Eye Adaptor native (Autodesk Fusion 360 design; units mm, degrees)
part number: 2026-10-13-21-17-23-938
Autodesk Fusion 360 part; units mm, degrees
ref_plane "WorkPlane1" through (0, 0, -5.95) normal (0, 0, 1) x (1, 0, 0)
sketch "Base" plane through (0, 0, -5.95) normal (0, 0, 1) x (1, 0, 0)
  circle A0 centre (0, 0) radius 11.7
  dimension "d80" = 23.4
  constraint coincident A0.centre origin
  measures "d80" diameter of A0
extrude "Eye Adaptor native" add sketch "Base" along normal mid plane 1.5 makes body 1
ref_plane "WorkPlane2" through (0, -1.05, 0) normal (0, 1, 0) x (0, 0, 1)
sketch "Side lug +X" plane through (0, -1.05, 0) normal (0, 1, 0) x (1, 0, 0)
  line L0 (3.609, 5.2) -> (3.609, 1.95)
  arc A0 (3.609, 1.95) -> (5.859, -0.3) centre (5.859, 1.95) ccw
  line L1 (5.859, -0.3) -> (6.949, -0.3)
  arc A1 (6.949, -0.3) -> (8.359, 1.9497) centre (5.8593, 1.9497) ccw
  line L2 (8.359, 1.9497) -> (8.359, 5.2)
  line L3 (8.359, 5.2) -> (3.609, 5.2)
  dimension "d81" = 2.25
  dimension "d82" = 2.4997
  dimension "d83" = 5.859
  dimension "d84" = 1.95
  dimension "d85" = 5.8593
  dimension "d86" = 1.9497
  dimension "d87" = 5.2
  constraint vertical L0
  constraint horizontal L1
  constraint vertical L2
  constraint horizontal L3
  constraint tangent L0 A0
  constraint tangent A0 L1
  constraint tangent A1 L2
  measures "d81" radius of A0
  measures "d82" radius of A1
  measures "d83" horizontal distance of origin A0.centre
  measures "d84" vertical distance of origin A0.centre
  measures "d85" horizontal distance of origin A1.centre
  measures "d86" vertical distance of origin A1.centre
  measures "d87" vertical distance of origin L0.start
extrude "Side lug +X (1)" add sketch "Side lug +X" along normal mid plane 4.1 separate body makes body 2
ref_plane "WorkPlane3" through (0, -1.05, 0) normal (0, 1, 0) x (0, 0, 1)
sketch "Side lug -X" plane through (0, -1.05, 0) normal (0, 1, 0) x (1, 0, 0)
  line L0 (-3.609, 5.2) -> (-3.609, 1.95)
  arc A0 (-5.859, -0.3) -> (-3.609, 1.95) centre (-5.859, 1.95) ccw
  line L1 (-5.859, -0.3) -> (-6.949, -0.3)
  arc A1 (-8.359, 1.9497) -> (-6.949, -0.3) centre (-5.8593, 1.9497) ccw
  line L2 (-8.359, 1.9497) -> (-8.359, 5.2)
  line L3 (-8.359, 5.2) -> (-3.609, 5.2)
  dimension "d88" = 2.25
  dimension "d89" = 2.4997
  dimension "d90" = 5.859
  dimension "d91" = 1.95
  dimension "d92" = 5.8593
  dimension "d93" = 1.9497
  dimension "d94" = 5.2
  constraint vertical L0
  constraint horizontal L1
  constraint vertical L2
  constraint horizontal L3
  constraint tangent L0 A0
  constraint tangent A0 L1
  constraint tangent A1 L2
  measures "d88" radius of A0
  measures "d89" radius of A1
  measures "d90" horizontal distance of origin A0.centre
  measures "d91" vertical distance of origin A0.centre
  measures "d92" horizontal distance of origin A1.centre
  measures "d93" vertical distance of origin A1.centre
  measures "d94" vertical distance of origin L0.start
extrude "Side lug -X (1)" add sketch "Side lug -X" along normal mid plane 4.1 separate body makes body 3
ref_plane "WorkPlane4" through (0, 0, -2.1) normal (0, 0, 1) x (1, 0, 0)
sketch "Gusset +X" plane through (0, 0, -2.1) normal (0, 0, 1) x (1, 0, 0)
  line L0 (3.5, -3) -> (8.1, -3)
  line L1 (8.1, -3) -> (3.5, -7.6)
  line L2 (3.5, -7.6) -> (3.5, -3)
  dimension "d95" = 3.5
  dimension "d96" = 3
  dimension "d97" = 8.1
  dimension "d98" = 7.6
  constraint horizontal L0
  constraint vertical L2
  measures "d95" horizontal distance of origin L0.start
  measures "d96" vertical distance of origin L0.start
  measures "d97" horizontal distance of origin L0.end
  measures "d98" vertical distance of origin L1.end
extrude "Gusset +X (1)" add sketch "Gusset +X" along normal mid plane 6.2 separate body makes body 4
ref_plane "WorkPlane5" through (0, -5.5, 0) normal (0, 1, 0) x (0, 0, 1)
sketch "Gusset dome +X" plane through (0, -5.5, 0) normal (0, 1, 0) x (1, 0, 0)
  line L0 (3.5, 5.2) -> (3.5, 0.024)
  line L1 (3.5, 0.024) -> (4.0825, 0.191)
  arc A0 (4.0825, 0.191) -> (8.359, 1.95) centre (5.859, 1.95) ccw
  line L2 (8.359, 1.95) -> (8.359, 5.2)
  line L3 (8.359, 5.2) -> (3.5, 5.2)
  dimension "d99" = 2.5
  dimension "d100" = 5.859
  dimension "d101" = 1.95
  dimension "d102" = 3.5
  dimension "d103" = 5.2
  dimension "d104" = 0.024
  dimension "d105" = 4.0825
  constraint vertical L0
  constraint vertical L2
  constraint horizontal L3
  constraint tangent A0 L2
  measures "d99" radius of A0
  measures "d100" horizontal distance of origin A0.centre
  measures "d101" vertical distance of origin A0.centre
  measures "d102" horizontal distance of origin L0.start
  measures "d103" vertical distance of origin L0.start
  measures "d104" vertical distance of origin L0.end
  measures "d105" horizontal distance of origin L1.end
extrude "Gusset dome +X (1)" add sketch "Gusset dome +X" along normal mid plane 5 separate body makes body 5
combine "Combine1" operation intersect target body 4 tool bodies 5
ref_plane "WorkPlane6" through (0, 0, -2.1) normal (0, 0, 1) x (1, 0, 0)
sketch "Gusset -X" plane through (0, 0, -2.1) normal (0, 0, 1) x (1, 0, 0)
  line L0 (-3.5, -3) -> (-8.1, -3)
  line L1 (-8.1, -3) -> (-3.5, -7.6)
  line L2 (-3.5, -7.6) -> (-3.5, -3)
  dimension "d106" = 3.5
  dimension "d107" = 3
  dimension "d108" = 8.1
  dimension "d109" = 7.6
  constraint horizontal L0
  constraint vertical L2
  measures "d106" horizontal distance of origin L0.start
  measures "d107" vertical distance of origin L0.start
  measures "d108" horizontal distance of origin L0.end
  measures "d109" vertical distance of origin L1.end
extrude "Gusset -X (1)" add sketch "Gusset -X" along normal mid plane 6.2 separate body makes body 6
ref_plane "WorkPlane7" through (0, -5.5, 0) normal (0, 1, 0) x (0, 0, 1)
sketch "Gusset dome -X" plane through (0, -5.5, 0) normal (0, 1, 0) x (1, 0, 0)
  line L0 (-3.5, 5.2) -> (-3.5, 0.024)
  line L1 (-3.5, 0.024) -> (-4.0825, 0.191)
  arc A0 (-8.359, 1.95) -> (-4.0825, 0.191) centre (-5.859, 1.95) ccw
  line L2 (-8.359, 1.95) -> (-8.359, 5.2)
  line L3 (-8.359, 5.2) -> (-3.5, 5.2)
  dimension "d110" = 2.5
  dimension "d111" = 5.859
  dimension "d112" = 1.95
  dimension "d113" = 3.5
  dimension "d114" = 5.2
  dimension "d115" = 0.024
  dimension "d116" = 4.0825
  constraint vertical L0
  constraint vertical L2
  constraint horizontal L3
  constraint tangent A0 L2
  measures "d110" radius of A0
  measures "d111" horizontal distance of origin A0.centre
  measures "d112" vertical distance of origin A0.centre
  measures "d113" horizontal distance of origin L0.start
  measures "d114" vertical distance of origin L0.start
  measures "d115" vertical distance of origin L0.end
  measures "d116" horizontal distance of origin L1.end
extrude "Gusset dome -X (1)" add sketch "Gusset dome -X" along normal mid plane 5 separate body makes body 7
combine "Combine2" operation intersect target body 6 tool bodies 7
ref_plane "WorkPlane8" through (0, -5.55, 0) normal (0, 1, 0) x (0, 0, 1)
sketch "Centre lug" plane through (0, -5.55, 0) normal (0, 1, 0) x (1, 0, 0)
  line L0 (-3.5, 5.2) -> (3.5, 5.2)
  line L1 (3.5, 5.2) -> (3.5, 0)
  arc A0 (-3.5, 0) -> (3.5, 0) centre (0, 0) ccw
  line L2 (-3.5, 0) -> (-3.5, 5.2)
  dimension "d117" = 3.5
  dimension "d118" = 5.2
  constraint horizontal L0
  constraint vertical L1
  constraint vertical L2
  constraint tangent L1 A0
  constraint tangent A0 L2
  constraint coincident A0.centre origin
  measures "d117" radius of A0
  measures "d118" vertical distance of A0.centre L0.start
extrude "Centre lug (1)" add sketch "Centre lug" along normal mid plane 5.1 separate body makes body 8
sketch "Centre ramp" plane through (0, 0, 0) normal (1, 0, 0) x (0, 0, -1)
  line L0 (5.2, -11.1) -> (5.2, -8.1)
  line L1 (5.2, -8.1) -> (0.2, -8.1)
  line L2 (0.2, -8.1) -> (5.2, -11.1)
  dimension "d119" = 5.2
  dimension "d120" = 11.1
  dimension "d121" = 8.1
  dimension "d122" = 0.2
  constraint vertical L0
  constraint horizontal L1
  measures "d119" horizontal distance of origin L0.start
  measures "d120" vertical distance of origin L0.start
  measures "d121" vertical distance of origin L0.end
  measures "d122" horizontal distance of origin L1.end
extrude "Centre ramp (1)" add sketch "Centre ramp" along normal mid plane 7 separate body makes body 9
sketch "Finger +X" plane through (0, 0, 0) normal (0, 1, 0) x (1, 0, 0)
  line L0 (8.652, 5.2) -> (8.946, 4.906)
  line L1 (8.946, 4.906) -> (10.3414, 4.3278)
  arc A0 (10.65, 3.866) -> (10.3414, 4.3278) centre (10.1501, 3.866) ccw
  line L2 (10.65, 3.866) -> (10.65, -3)
  line L3 (10.65, -3) -> (11.7, -3)
  line L4 (11.7, -3) -> (11.7, 5.2)
  line L5 (11.7, 5.2) -> (8.652, 5.2)
  dimension "d123" = 0.4999
  dimension "d124" = 10.1501
  dimension "d125" = 3.866
  dimension "d126" = 8.652
  dimension "d127" = 5.2
  dimension "d128" = 8.946
  dimension "d129" = 4.906
  dimension "d130" = 3
  dimension "d131" = 11.7
  constraint vertical L2
  constraint horizontal L3
  constraint vertical L4
  constraint horizontal L5
  constraint tangent L1 A0
  constraint tangent A0 L2
  measures "d123" radius of A0
  measures "d124" horizontal distance of origin A0.centre
  measures "d125" vertical distance of origin A0.centre
  measures "d126" horizontal distance of origin L0.start
  measures "d127" vertical distance of origin L0.start
  measures "d128" horizontal distance of origin L0.end
  measures "d129" vertical distance of origin L0.end
  measures "d130" vertical distance of origin L2.end
  measures "d131" horizontal distance of origin L3.end
revolve "Finger +X (1)" add sketch "Finger +X" angle 360 about axis through (0, 0, 1.75) along (0, 0, 1) separate body makes body 10
sketch "Finger Q +X" plane through (0, 0, 0) normal (0, 1, 0) x (1, 0, 0)
  line L0 (5.011, 5.5) -> (5.011, 5.2)
  arc A0 (5.761, 4.45) -> (5.011, 5.2) centre (5.011, 4.45) ccw
  line L1 (5.761, 4.45) -> (5.761, -0.5)
  arc A1 (5.761, -0.5) -> (7.761, -2.5) centre (7.761, -0.5) ccw
  line L2 (7.761, -2.5) -> (13, -2.5)
  line L3 (13, -2.5) -> (13, 5.5)
  line L4 (13, 5.5) -> (5.011, 5.5)
  dimension "d132" = 0.75
  dimension "d133" = 2
  dimension "d134" = 5.011
  dimension "d135" = 4.45
  dimension "d136" = 0.5
  dimension "d137" = 5.011
  dimension "d138" = 5.5
  dimension "d139" = 13
  constraint vertical L0
  constraint vertical L1
  constraint horizontal L2
  constraint vertical L3
  constraint horizontal L4
  constraint tangent A0 L1
  constraint tangent L1 A1
  constraint tangent A1 L2
  measures "d132" radius of A0
  measures "d133" radius of A1
  measures "d134" horizontal distance of origin A0.centre
  measures "d135" vertical distance of origin A0.centre
  measures "d136" vertical distance of origin A1.centre
  measures "d137" horizontal distance of origin L0.start
  measures "d138" vertical distance of origin L0.start
  measures "d139" horizontal distance of origin L2.end
extrude "Finger Q +X (1)" add sketch "Finger Q +X" along normal mid plane 28 separate body makes body 11
combine "Combine3" operation intersect target body 10 tool bodies 11
ref_plane "WorkPlane9" through (9, 0, 0) normal (1, 0, 0) x (0, 1, 0)
sketch "Finger S +X" plane through (9, 0, 0) normal (1, 0, 0) x (0, 0, -1)
  line L0 (5.5, -13) -> (5.5, 13)
  line L1 (5.5, 13) -> (-2.5, 13)
  line L2 (-2.5, 13) -> (-2.5, 5.2943)
  arc A0 (-0.8431, 2.7656) -> (-2.5, 5.2943) centre (-7.7818, 0.0264) ccw
  arc A1 (-0.8431, 2.7656) -> (1.0172, 1.5) centre (1.0172, 3.5) ccw
  line L3 (1.0172, 1.5) -> (3.7, 1.5)
  arc A2 (3.7, -1.5) -> (3.7, 1.5) centre (3.7, 0) ccw
  line L4 (3.7, -1.5) -> (0.9961, -1.5)
  arc A3 (0.9961, -1.5) -> (-0.8597, -2.7544) centre (0.9961, -3.5) ccw
  arc A4 (-2.5, -5.2415) -> (-0.8597, -2.7544) centre (-7.7818, 0.0264) ccw
  line L5 (-2.5, -5.2415) -> (-2.5, -13)
  line L6 (-2.5, -13) -> (5.5, -13)
  dimension "d140" = 7.4598
  dimension "d141" = 2
  dimension "d142" = 1.5
  dimension "d143" = 7.7818
  dimension "d144" = 0.0264
  dimension "d145" = 1.0172
  dimension "d146" = 3.7
  dimension "d147" = 5.5
  dimension "d148" = 13
  dimension "d149" = 13
  dimension "d150" = 2.5
  dimension "d151" = 2.5
  constraint vertical L0
  constraint horizontal L1
  constraint vertical L2
  constraint horizontal L3
  constraint horizontal L4
  constraint vertical L5
  constraint horizontal L6
  constraint tangent A0 A1
  constraint tangent A1 L3
  constraint tangent L3 A2
  constraint tangent A2 L4
  constraint tangent L4 A3
  constraint tangent A3 A4
  constraint coincident A0.centre A4.centre
  constraint equal A1 A3
  constraint equal A0 A4
  measures "d140" radius of A0
  measures "d141" radius of A1
  measures "d142" radius of A2
  measures "d143" horizontal distance of origin A0.centre
  measures "d144" vertical distance of origin A0.centre
  measures "d145" horizontal distance of origin A1.centre
  measures "d146" horizontal distance of origin A2.centre
  measures "d147" horizontal distance of origin L0.start
  measures "d148" vertical distance of origin L0.start
  measures "d149" vertical distance of origin L0.end
  measures "d150" horizontal distance of origin L1.end
  measures "d151" horizontal distance of origin A4.start
extrude "Finger S +X (1)" add sketch "Finger S +X" along normal mid plane 8 separate body makes body 12
combine "Combine4" operation intersect target body 10 tool bodies 12
sketch "Finger -X" plane through (0, 0, 0) normal (0, 1, 0) x (1, 0, 0)
  line L0 (8.652, 5.2) -> (8.946, 4.906)
  line L1 (8.946, 4.906) -> (10.3414, 4.3278)
  arc A0 (10.65, 3.866) -> (10.3414, 4.3278) centre (10.1501, 3.866) ccw
  line L2 (10.65, 3.866) -> (10.65, -3)
  line L3 (10.65, -3) -> (11.7, -3)
  line L4 (11.7, -3) -> (11.7, 5.2)
  line L5 (11.7, 5.2) -> (8.652, 5.2)
  dimension "d152" = 0.4999
  dimension "d153" = 10.1501
  dimension "d154" = 3.866
  dimension "d155" = 8.652
  dimension "d156" = 5.2
  dimension "d157" = 8.946
  dimension "d158" = 4.906
  dimension "d159" = 3
  dimension "d160" = 11.7
  constraint vertical L2
  constraint horizontal L3
  constraint vertical L4
  constraint horizontal L5
  constraint tangent L1 A0
  constraint tangent A0 L2
  measures "d152" radius of A0
  measures "d153" horizontal distance of origin A0.centre
  measures "d154" vertical distance of origin A0.centre
  measures "d155" horizontal distance of origin L0.start
  measures "d156" vertical distance of origin L0.start
  measures "d157" horizontal distance of origin L0.end
  measures "d158" vertical distance of origin L0.end
  measures "d159" vertical distance of origin L2.end
  measures "d160" horizontal distance of origin L3.end
revolve "Finger -X (1)" add sketch "Finger -X" angle 360 about axis through (0, 0, 1.75) along (0, 0, 1) separate body makes body 13
sketch "Finger Q -X" plane through (0, 0, 0) normal (0, 1, 0) x (1, 0, 0)
  line L0 (-13, 5.5) -> (-7.019, 5.5)
  line L1 (-7.019, 5.5) -> (-7.019, 5.2)
  line L2 (-7.019, 5.2) -> (-8.019, 4.2)
  line L3 (-8.019, 4.2) -> (-8.019, -1)
  arc A0 (-9.519, -2.5) -> (-8.019, -1) centre (-9.519, -1) ccw
  line L4 (-9.519, -2.5) -> (-13, -2.5)
  line L5 (-13, -2.5) -> (-13, 5.5)
  dimension "d161" = 1.5
  dimension "d162" = 9.519
  dimension "d163" = 1
  dimension "d164" = 13
  dimension "d165" = 5.5
  dimension "d166" = 7.019
  dimension "d167" = 5.2
  dimension "d168" = 4.2
  constraint horizontal L0
  constraint vertical L1
  constraint vertical L3
  constraint horizontal L4
  constraint vertical L5
  constraint tangent L3 A0
  constraint tangent A0 L4
  measures "d161" radius of A0
  measures "d162" horizontal distance of origin A0.centre
  measures "d163" vertical distance of origin A0.centre
  measures "d164" horizontal distance of origin L0.start
  measures "d165" vertical distance of origin L0.start
  measures "d166" horizontal distance of origin L0.end
  measures "d167" vertical distance of origin L1.end
  measures "d168" vertical distance of origin L2.end
extrude "Finger Q -X (1)" add sketch "Finger Q -X" along normal mid plane 28 separate body makes body 14
combine "Combine5" operation intersect target body 13 tool bodies 14
ref_plane "WorkPlane10" through (-9, 0, 0) normal (1, 0, 0) x (0, 1, 0)
sketch "Finger S -X" plane through (-9, 0, 0) normal (1, 0, 0) x (0, 0, -1)
  line L0 (5.5, -13) -> (5.5, 13)
  line L1 (5.5, 13) -> (-2.5, 13)
  line L2 (-2.5, 13) -> (-2.5, 5.2943)
  arc A0 (-2.5, -5.2415) -> (-2.5, 5.2943) centre (-7.7818, 0.0264) ccw
  line L3 (-2.5, -5.2415) -> (-2.5, -13)
  line L4 (-2.5, -13) -> (5.5, -13)
  dimension "d169" = 7.4598
  dimension "d170" = 7.7818
  dimension "d171" = 0.0264
  dimension "d172" = 5.5
  dimension "d173" = 13
  dimension "d174" = 13
  dimension "d175" = 2.5
  dimension "d176" = 2.5
  constraint vertical L0
  constraint horizontal L1
  constraint vertical L2
  constraint vertical L3
  constraint horizontal L4
  measures "d169" radius of A0
  measures "d170" horizontal distance of origin A0.centre
  measures "d171" vertical distance of origin A0.centre
  measures "d172" horizontal distance of origin L0.start
  measures "d173" vertical distance of origin L0.start
  measures "d174" vertical distance of origin L0.end
  measures "d175" horizontal distance of origin L1.end
  measures "d176" horizontal distance of origin A0.start
extrude "Finger S -X (1)" add sketch "Finger S -X" along normal mid plane 8 separate body makes body 15
combine "Combine6" operation intersect target body 13 tool bodies 15
sketch "Barb 19.5" plane through (0, 0, 0) normal (0, 1, 0) x (1, 0, 0)
  line L0 (11.7, 4.753) -> (12.199, 1.124)
  line L1 (12.199, 1.124) -> (12.199, -0.376)
  line L2 (12.199, -0.376) -> (11.7, -0.376)
  line L3 (11.7, -0.376) -> (11.7, 4.753)
  dimension "d177" = 11.7
  dimension "d178" = 4.753
  dimension "d179" = 12.199
  dimension "d180" = 1.124
  dimension "d181" = 0.376
  constraint vertical L1
  constraint horizontal L2
  constraint vertical L3
  measures "d177" horizontal distance of origin L0.start
  measures "d178" vertical distance of origin L0.start
  measures "d179" horizontal distance of origin L0.end
  measures "d180" vertical distance of origin L0.end
  measures "d181" vertical distance of origin L1.end
revolve "Barb 19.5 (1)" add sketch "Barb 19.5" angle 360 about axis through (0, 0, 1.75) along (0, 0, 1) separate body makes body 16
ref_plane "WorkPlane11" through (0, 0, -2) normal (0, 0, 1) x (1, 0, 0)
sketch "Barb sector 19.5" plane through (0, 0, -2) normal (0, 0, 1) x (1, 0, 0)
  line L0 (0, 0) -> (13.197, 4.6733)
  arc A0 (13.197, 4.6733) -> (6.8939, 12.185) centre (0, 0) ccw
  line L1 (6.8939, 12.185) -> (0, 0)
  dimension "d182" = 14
  dimension "d183" = 13.197
  dimension "d184" = 6.8939
  constraint coincident L0.start A0.centre
  constraint vertical L0.start A0.centre
  constraint horizontal L0.start A0.centre
  measures "d182" radius of A0
  measures "d183" horizontal distance of L0.start L0.end
  measures "d184" horizontal distance of L0.start A0.end
extrude "Barb sector 19.5 (1)" add sketch "Barb sector 19.5" along normal mid plane 12 separate body makes body 17
combine "Combine7" operation intersect target body 16 tool bodies 17
sketch "Barb -60.5" plane through (0, 0, 0) normal (0, 1, 0) x (1, 0, 0)
  line L0 (11.7, 4.753) -> (12.199, 1.124)
  line L1 (12.199, 1.124) -> (12.199, -0.376)
  line L2 (12.199, -0.376) -> (11.7, -0.376)
  line L3 (11.7, -0.376) -> (11.7, 4.753)
  dimension "d185" = 11.7
  dimension "d186" = 4.753
  dimension "d187" = 12.199
  dimension "d188" = 1.124
  dimension "d189" = 0.376
  constraint vertical L1
  constraint horizontal L2
  constraint vertical L3
  measures "d185" horizontal distance of origin L0.start
  measures "d186" vertical distance of origin L0.start
  measures "d187" horizontal distance of origin L0.end
  measures "d188" vertical distance of origin L0.end
  measures "d189" vertical distance of origin L1.end
revolve "Barb -60.5 (1)" add sketch "Barb -60.5" angle 360 about axis through (0, 0, 1.75) along (0, 0, 1) separate body makes body 18
ref_plane "WorkPlane12" through (0, 0, -2) normal (0, 0, 1) x (1, 0, 0)
sketch "Barb sector -60.5" plane through (0, 0, -2) normal (0, 0, 1) x (1, 0, 0)
  line L0 (0, 0) -> (6.8939, -12.185)
  arc A0 (6.8939, -12.185) -> (13.197, -4.6733) centre (0, 0) ccw
  line L1 (13.197, -4.6733) -> (0, 0)
  dimension "d190" = 14
  dimension "d191" = 6.8939
  dimension "d192" = 13.197
  constraint coincident L0.start A0.centre
  constraint vertical L0.start A0.centre
  constraint horizontal L0.start A0.centre
  measures "d190" radius of A0
  measures "d191" horizontal distance of L0.start L0.end
  measures "d192" horizontal distance of L0.start A0.end
extrude "Barb sector -60.5 (1)" add sketch "Barb sector -60.5" along normal mid plane 12 separate body makes body 19
combine "Combine8" operation intersect target body 18 tool bodies 19
sketch "Barb 134.5" plane through (0, 0, 0) normal (0, 1, 0) x (1, 0, 0)
  line L0 (11.7, 4.753) -> (12.199, 1.124)
  line L1 (12.199, 1.124) -> (12.199, -0.376)
  line L2 (12.199, -0.376) -> (11.7, -0.376)
  line L3 (11.7, -0.376) -> (11.7, 4.753)
  dimension "d193" = 11.7
  dimension "d194" = 4.753
  dimension "d195" = 12.199
  dimension "d196" = 1.124
  dimension "d197" = 0.376
  constraint vertical L1
  constraint horizontal L2
  constraint vertical L3
  measures "d193" horizontal distance of origin L0.start
  measures "d194" vertical distance of origin L0.start
  measures "d195" horizontal distance of origin L0.end
  measures "d196" vertical distance of origin L0.end
  measures "d197" vertical distance of origin L1.end
revolve "Barb 134.5 (1)" add sketch "Barb 134.5" angle 360 about axis through (0, 0, 1.75) along (0, 0, 1) separate body makes body 20
ref_plane "WorkPlane13" through (0, 0, -2) normal (0, 0, 1) x (1, 0, 0)
sketch "Barb sector 134.5" plane through (0, 0, -2) normal (0, 0, 1) x (1, 0, 0)
  line L0 (0, 0) -> (-9.8127, 9.9855)
  arc A0 (-9.8127, 9.9855) -> (-9.8127, -9.9855) centre (0, 0) ccw
  line L1 (-9.8127, -9.9855) -> (0, 0)
  dimension "d198" = 14
  dimension "d199" = 9.8127
  dimension "d200" = 9.8127
  constraint coincident L0.start A0.centre
  constraint vertical L0.start A0.centre
  constraint horizontal L0.start A0.centre
  measures "d198" radius of A0
  measures "d199" horizontal distance of L0.start L0.end
  measures "d200" horizontal distance of L0.start A0.end
extrude "Barb sector 134.5 (1)" add sketch "Barb sector 134.5" along normal mid plane 12 separate body makes body 21
combine "Combine9" operation intersect target body 20 tool bodies 21
combine "Join all" operation add target body 1 tool bodies 2 3 4 6 8 9 10 13 16 18 20
ref_plane "WorkPlane14" through (0, -1, 0) normal (0, 1, 0) x (0, 0, 1)
sketch "Lug hole +1" plane through (0, -1, 0) normal (0, 1, 0) x (1, 0, 0)
  circle A0 centre (5.859, 1.95) radius 1.5
  dimension "d201" = 3
  dimension "d202" = 5.859
  dimension "d203" = 1.95
  measures "d201" diameter of A0
  measures "d202" horizontal distance of origin A0.centre
  measures "d203" vertical distance of origin A0.centre
extrude "Extrude17" cut sketch "Lug hole +1" along normal mid plane 4 bodies 1
ref_plane "WorkPlane15" through (0, -1, 0) normal (0, 1, 0) x (0, 0, 1)
sketch "Lug hole -1" plane through (0, -1, 0) normal (0, 1, 0) x (1, 0, 0)
  circle A0 centre (-5.859, 1.95) radius 1.5
  dimension "d204" = 3
  dimension "d205" = 5.859
  dimension "d206" = 1.95
  measures "d204" diameter of A0
  measures "d205" horizontal distance of origin A0.centre
  measures "d206" vertical distance of origin A0.centre
extrude "Extrude18" cut sketch "Lug hole -1" along normal mid plane 4 bodies 1
ref_plane "WorkPlane16" through (0, -5.5, 0) normal (0, 1, 0) x (0, 0, 1)
sketch "Centre hole" plane through (0, -5.5, 0) normal (0, 1, 0) x (1, 0, 0)
  circle A0 centre (0, 0) radius 1.5
  dimension "d207" = 3
  constraint coincident A0.centre origin
  measures "d207" diameter of A0
extrude "Extrude19" cut sketch "Centre hole" along normal mid plane 5 bodies 1
ref_plane "WorkPlane17" through (0, 0, -1.5) normal (0, 0, 1) x (1, 0, 0)
sketch "Rib slot" plane through (0, 0, -1.5) normal (0, 0, 1) x (1, 0, 0)
  line L0 (-14, -0.925) -> (-11.3654, -0.925)
  arc A0 (-11.3654, -0.925) -> (-11.3654, 0.925) centre (-11.3654, 0) ccw
  line L1 (-11.3654, 0.925) -> (-14, 0.925)
  line L2 (-14, 0.925) -> (-14, -0.925)
  dimension "d208" = 0.925
  dimension "d209" = 11.3654
  dimension "d210" = 14
  constraint horizontal L0
  constraint horizontal L1
  constraint vertical L2
  constraint tangent L0 A0
  constraint tangent A0 L1
  constraint horizontal origin A0.centre
  measures "d208" radius of A0
  measures "d209" horizontal distance of origin A0.centre
  measures "d210" horizontal distance of origin L0.start
extrude "Rib slot (1)" cut sketch "Rib slot" along normal mid plane 13 bodies 1
named bodies: "Eye Adaptor native", "Side lug +X", "Side lug -X", "Gusset +X", "Gusset dome +X", "Gusset -X", "Gusset dome -X", "Centre lug", "Centre ramp", "Finger +X", "Finger Q +X", "Finger S +X", "Finger -X", "Finger Q -X", "Finger S -X", "Barb 19.5", "Barb sector 19.5", "Barb -60.5", "Barb sector -60.5", "Barb 134.5", "Barb sector 134.5"
